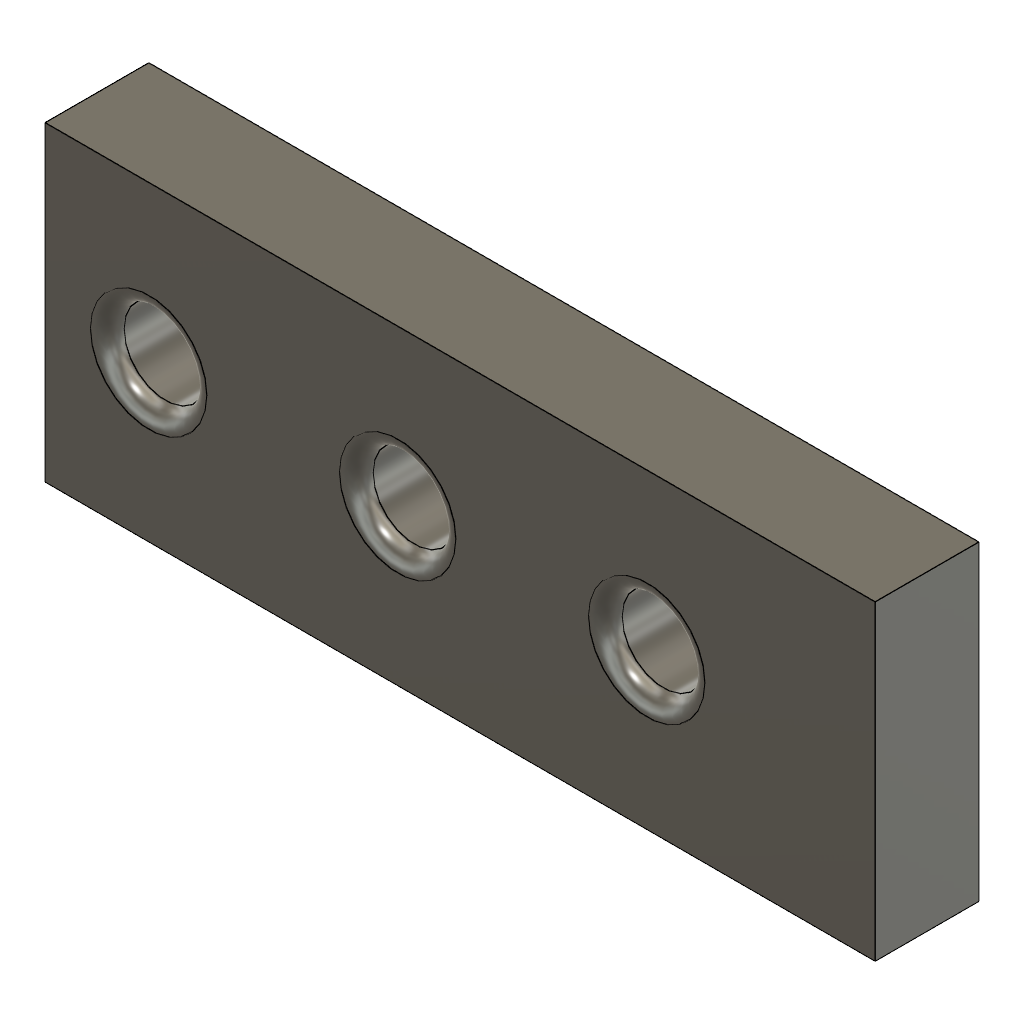
fillet_after_pattern (Autodesk Fusion 360 design; units mm, degrees)
part number: 2026-11-12-22-56-47-767
Autodesk Fusion 360 part; units mm, degrees
sketch "Sketch1" plane through (0, 0, 0) normal (0, 0, 1) x (1, 0, 0)
  line L0 (0, 0) -> (40, 0)
  line L1 (40, 0) -> (40, 15)
  line L2 (40, 15) -> (0, 15)
  line L3 (0, 15) -> (0, 0)
extrude "Extrude1" add sketch "Sketch1" along normal blind 5
sketch "Sketch2" plane through (0, 0, 0) normal (0, 0, 1) x (1, 0, 0)
  circle A0 centre (5, 7.5) radius 2
extrude "Extrude2" cut sketch "Sketch2" along normal through all
pattern_linear "R-Pattern1" count 3 spacing 12 along (1, 0, 0) count 3 spacing 0 along (1, 0, 0) of "Extrude2"
fillet "Fillet1" radius 0.8 3 edges at (27.1353, 8.2232, 5) (15.1353, 8.2232, 5) (3.1353, 8.2232, 5)
